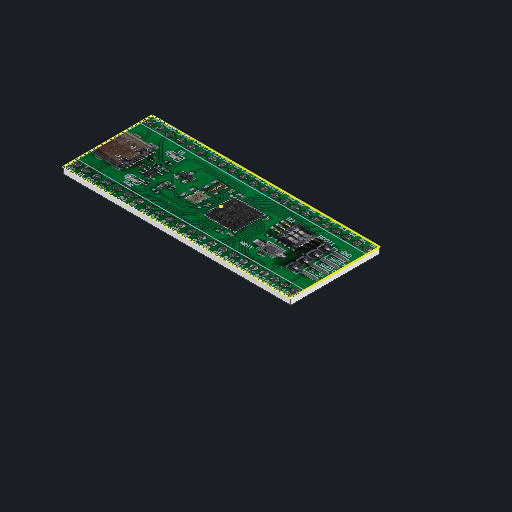
# Autodesk Inventor part: MainBoard
Saved by Autodesk Inventor 2027.1 (Build 311270010, 270A)
## iProperties
Created: 2024-04-23
Part Number: MainBoard
Material: ABS Plastic
Document SubType Name: Modeling
Designer: - LENOVO -
Density: 1.06 g/cm^3
Appearance: Smooth - White
Author: - LENOVO -
Autodesk Inventor part; units mm, degrees
ref_plane "YZ Plane" through (0, 0, 0) normal (1, 0, 0) x (0, 1, 0)
ref_plane "XZ Plane" through (0, 0, 0) normal (0, 1, 0) x (-1, 0, 0)
ref_plane "XY Plane" through (0, 0, 0) normal (0, 0, 1) x (1, 0, 0)
sketch "Sketch1" plane through (0, 0, 0) normal (0, 1, 0) x (-1, 0, 0)
  line L0 (28, -10.95) -> (-28, -10.95)
  line L1 (-28, -10.95) -> (-28, 10.95)
  line L2 (-28, 10.95) -> (28, 10.95)
  line L3 (28, 10.95) -> (28, -10.95)
  line L4 (28, -10.95) -> (-28, 10.95) construction
  line L5 (-28, -10.95) -> (28, 10.95) construction
  point P0 (0, 0)
  dimension "d0" = 56
  dimension "d1" = 21.9
  constraints: 12 end point, 2 midpoint, 2 parallel, 1 horizontal, 1 perpendicular
  measures "d0" distance of L1.end L2.end
  measures "d1" distance of L0.end L1.end
extrude "Extrusion1" add sketch "Sketch1" against normal blind 1.5
sketch "Sketch2" plane through (0, 0, 0) normal (0, 1, 0) x (1, 0, 0)
  line L0 (-28, -10.95) -> (-28, 10.95) projected
  line L1 (-28, 10.95) -> (27.9613, 11.0486) construction
  line L2 (27.9613, 11.0486) -> (28, -10.95) construction
  line L3 (28, -10.95) -> (-27.9613, -11.0486) construction
  line L4 (-27.9613, -11.0486) -> (-28, 10.95) construction
  line L5 (28, 10.95) -> (28, -10.95) projected
  line L6 (28, -10.95) -> (-28, -10.95) projected
  line L7 (-28, -10.95) -> (-28, 10.95) projected
  line L8 (-28, 10.95) -> (28, 10.95) projected
  point P0 (0, 0)
  constraints: 1 coincident, 2 other
sketch "Sketch3" plane through (0, 0, 0) normal (0, 1, 0) x (1, 0, 0)
  circle A0 centre (-26.67, 8.89) radius 0.5
  line L0 (-26.67, 8.89) -> (-25.0862, 8.89)
  line L1 (-26.67, 8.89) -> (-26.67, 7.3054)
  circle A1 centre (-24.13, 8.89) radius 0.5
  circle A2 centre (-21.59, 8.89) radius 0.5
  circle A3 centre (-19.05, 8.89) radius 0.5
  circle A4 centre (-16.51, 8.89) radius 0.5
  circle A5 centre (-13.97, 8.89) radius 0.5
  circle A6 centre (-11.43, 8.89) radius 0.5
  circle A7 centre (-8.89, 8.89) radius 0.5
  circle A8 centre (-6.35, 8.89) radius 0.5
  circle A9 centre (-3.81, 8.89) radius 0.5
  circle A10 centre (-1.27, 8.89) radius 0.5
  circle A11 centre (1.27, 8.89) radius 0.5
  circle A12 centre (3.81, 8.89) radius 0.5
  circle A13 centre (6.35, 8.89) radius 0.5
  circle A14 centre (8.89, 8.89) radius 0.5
  circle A15 centre (11.43, 8.89) radius 0.5
  circle A16 centre (13.97, 8.89) radius 0.5
  circle A17 centre (16.51, 8.89) radius 0.5
  circle A18 centre (19.05, 8.89) radius 0.5
  circle A19 centre (21.59, 8.89) radius 0.5
  circle A20 centre (24.13, 8.89) radius 0.5
  circle A21 centre (26.67, 8.89) radius 0.5
  circle A22 centre (-26.67, -8.89) radius 0.5
  circle A23 centre (-24.13, -8.89) radius 0.5
  circle A24 centre (-21.59, -8.89) radius 0.5
  circle A25 centre (-19.05, -8.89) radius 0.5
  circle A26 centre (-16.51, -8.89) radius 0.5
  circle A27 centre (-13.97, -8.89) radius 0.5
  circle A28 centre (-11.43, -8.89) radius 0.5
  circle A29 centre (-8.89, -8.89) radius 0.5
  circle A30 centre (-6.35, -8.89) radius 0.5
  circle A31 centre (-3.81, -8.89) radius 0.5
  circle A32 centre (-1.27, -8.89) radius 0.5
  circle A33 centre (1.27, -8.89) radius 0.5
  circle A34 centre (3.81, -8.89) radius 0.5
  circle A35 centre (6.35, -8.89) radius 0.5
  circle A36 centre (8.89, -8.89) radius 0.5
  circle A37 centre (11.43, -8.89) radius 0.5
  circle A38 centre (13.97, -8.89) radius 0.5
  circle A39 centre (16.51, -8.89) radius 0.5
  circle A40 centre (19.05, -8.89) radius 0.5
  circle A41 centre (21.59, -8.89) radius 0.5
  circle A42 centre (24.13, -8.89) radius 0.5
  circle A43 centre (26.67, -8.89) radius 0.5
  line L2 (-26.67, 8.89) -> (-26.67, -8.89) construction
  line L3 (-26.67, 8.89) -> (26.67, 8.89) construction
  line L4 (28, 10.95) -> (-28, 10.95) construction
  line L5 (-28, 10.95) -> (-28, -10.95) construction
  point P0 (0, 0)
  point P1 (0, 8.89)
  point P2 (0, 10.95)
  point P3 (-26.67, 0)
  point P4 (-28, 0)
  dimension "d7" = 1
  dimension "d10" = 2.54
  dimension "d13" = 17.78
  constraints: 44 centre point, 8 end point, 4 midpoint, 3 horizontal, 3 vertical, 1 horizontal alignment, 1 vertical alignment, 86 other
  measures "d7" diameter of A0
  measures "d10" distance of L0.start A1.centre
  measures "d13" distance of L0.start L2.end
extrude "Extrusion2" cut sketch "Sketch3" against normal blind 1.5
body "Solid1"
